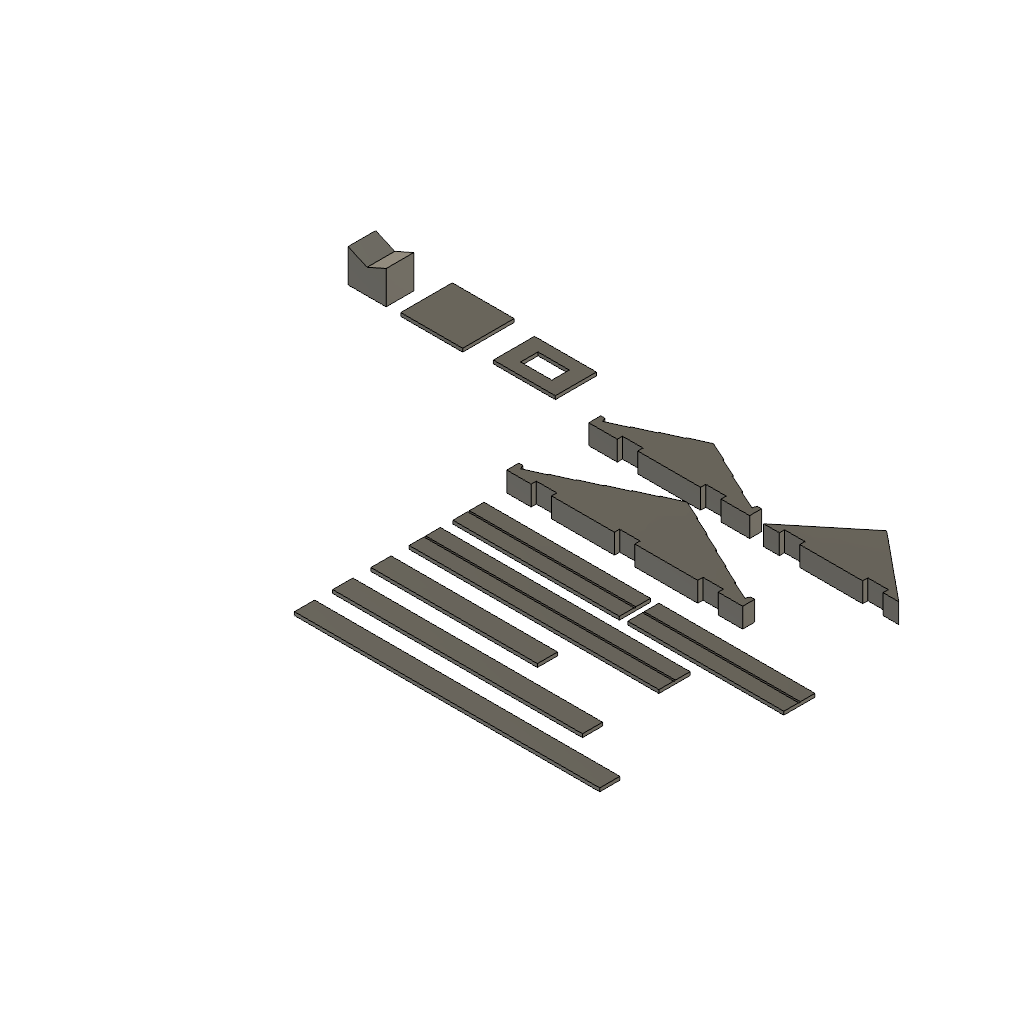
DeadPresidentTreeSections_roof_parts (Autodesk Fusion 360 design; units mm, degrees)
part number: 2026-11-12-23-33-05-956
part number: 2026-11-12-23-33-08-958
part number: 2026-11-12-23-33-09-476
part number: 2026-11-12-23-33-09-794
part number: 2026-11-12-23-33-09-946
part number: 2026-11-12-23-33-10-021
part number: 2026-11-12-23-33-10-090
part number: 2026-11-12-23-33-10-162
part number: 2026-11-12-23-33-10-314
part number: 2026-11-12-23-33-10-475
part number: 2026-11-12-23-33-10-651
part number: 2026-11-12-23-33-10-935
part number: 2026-11-12-23-33-11-042
Autodesk Fusion 360 part; units mm, degrees
sketch "Half profile" plane through (0, 0, 0) normal (0, 0, 1) x (1, 0, 0) in component "gable_plastic_8-1_2"
  line L0 (0, 0) -> (107.95, 0)
  line L1 (107.95, 0) -> (107.95, 57.95)
  line L2 (107.95, 57.95) -> (5.4, 7.5)
  line L3 (5.4, 7.5) -> (3.7975, 11.1)
  line L4 (3.7975, 11.1) -> (0, 11.1)
  line L5 (0, 11.1) -> (0, 0)
  dimension "d46" = 107.95
  dimension "d47" = 57.95
  dimension "d48" = 5.4
  dimension "d49" = 7.5
  dimension "d50" = 3.7975
  dimension "d51" = 11.1
  constraint coincident L0.start L5.end
  constraint horizontal L0.start L0.end
  constraint vertical L0.end L1.end
  constraint vertical L0.start L4.end
  constraint horizontal L3.end L4.end
  measures "d46" horizontal distance of L0.start L0.end
  measures "d47" vertical distance of L0.start L1.end
  measures "d48" horizontal distance of L0.start L2.end
  measures "d49" vertical distance of L0.start L2.end
  measures "d50" horizontal distance of L0.start L3.end
  measures "d51" vertical distance of L0.start L3.end
extrude "Half gable" add sketch "Half profile" along normal blind 18.25 makes body 1 in component "gable_plastic_8-1_2"
sketch "Step" plane through (0, 0, 0) normal (0, 0, 1) x (1, 0, 0) in component "gable_plastic_8-1_2"
  line L0 (5.4, 7.5) -> (22.4917, 15.9083)
  line L1 (22.4917, 15.9083) -> (22.4917, 15.1083)
  line L2 (22.4917, 15.1083) -> (5.4, 7.5)
  dimension "d54" = 5.4
  dimension "d55" = 7.5
  dimension "d56" = 22.4917
  dimension "d57" = 15.9083
  dimension "d58" = 15.1083
  constraint vertical L0.end L1.end
  measures "d54" horizontal distance of origin L0.start
  measures "d55" vertical distance of origin L0.start
  measures "d56" horizontal distance of origin L0.end
  measures "d57" vertical distance of origin L0.end
  measures "d58" vertical distance of origin L1.end
extrude "Step cut" cut sketch "Step" along normal blind 18.25 bodies 1 in component "gable_plastic_8-1_2"
pattern_linear "Step pattern" count 6 spacing 19.048 along (0.897296, 0.441429, 0) count 3 spacing 0 along (0.897296, 0.441429, 0) of "Step cut" in component "gable_plastic_8-1_2"
ref_plane "WorkPlane1" through (107.95, 0, 0) normal (1, 0, 0) x (0, 1, 0) in component "gable_plastic_8-1_2"
mirror "Mirror half" about plane through (107.95, 0, 0) normal (1, 0, 0) of bodies 1 merged in component "gable_plastic_8-1_2"
sketch "Notch" plane through (0, 0, 0) normal (0, 0, 1) x (1, 0, 0) in component "gable_plastic_8-1_2"
  line L0 (22.425, -1) -> (41.075, -1)
  line L1 (41.075, -1) -> (41.075, 4.7625)
  line L2 (41.075, 4.7625) -> (22.425, 4.7625)
  line L3 (22.425, 4.7625) -> (22.425, -1)
  dimension "d69" = 22.425
  dimension "d70" = 1
  dimension "d71" = 41.075
  dimension "d72" = 4.7625
  constraint horizontal L0
  constraint vertical L1
  constraint horizontal L2
  constraint vertical L3
  measures "d69" horizontal distance of origin L0.start
  measures "d70" vertical distance of origin L0.start
  measures "d71" horizontal distance of origin L1.end
  measures "d72" vertical distance of origin L1.end
extrude "Notch cut" cut sketch "Notch" along normal blind 18.25 bodies 1 in component "gable_plastic_8-1_2"
pattern_linear "Notch pattern" count 3 spacing 76.2 along (1, 0, 0) count 3 spacing 0 along (1, 0, 0) of "Notch cut" in component "gable_plastic_8-1_2"
sketch "Half profile (2)" plane through (0, 0, 0) normal (0, 0, 1) x (1, 0, 0) in component "gable_plastic_small_2notch"
  line L0 (0, 0) -> (73.66, 0)
  line L1 (73.66, 0) -> (73.66, 41.3718)
  line L2 (73.66, 41.3718) -> (5.4, 7.5)
  line L3 (5.4, 7.5) -> (3.7824, 11.1)
  line L4 (3.7824, 11.1) -> (0, 11.1)
  line L5 (0, 11.1) -> (0, 0)
  dimension "d79" = 73.66
  dimension "d80" = 41.3718
  dimension "d81" = 5.4
  dimension "d82" = 7.5
  dimension "d83" = 3.7824
  dimension "d84" = 11.1
  constraint coincident L0.start L5.end
  constraint horizontal L0.start L0.end
  constraint vertical L0.end L1.end
  constraint vertical L0.start L4.end
  constraint horizontal L3.end L4.end
  measures "d79" horizontal distance of L0.start L0.end
  measures "d80" vertical distance of L0.start L1.end
  measures "d81" horizontal distance of L0.start L2.end
  measures "d82" vertical distance of L0.start L2.end
  measures "d83" horizontal distance of L0.start L3.end
  measures "d84" vertical distance of L0.start L3.end
extrude "Half gable'" add sketch "Half profile (2)" along normal blind 18.25 separate body makes body 2 in component "gable_plastic_small_2notch"
sketch "Step (2)" plane through (0, 0, 0) normal (0, 0, 1) x (1, 0, 0) in component "gable_plastic_small_2notch"
  line L0 (5.4, 7.5) -> (22.465, 15.968)
  line L1 (22.465, 15.968) -> (22.465, 15.168)
  line L2 (22.465, 15.168) -> (5.4, 7.5)
  dimension "d87" = 5.4
  dimension "d88" = 7.5
  dimension "d89" = 22.465
  dimension "d90" = 15.968
  dimension "d91" = 15.168
  constraint vertical L0.end L1.end
  measures "d87" horizontal distance of origin L0.start
  measures "d88" vertical distance of origin L0.start
  measures "d89" horizontal distance of origin L0.end
  measures "d90" vertical distance of origin L0.end
  measures "d91" vertical distance of origin L1.end
extrude "Step cut'" cut sketch "Step (2)" along normal blind 18.25 bodies 2 in component "gable_plastic_small_2notch"
pattern_linear "Step pattern'" count 4 spacing 19.0505 along (0.895778, 0.444501, 0) count 3 spacing 0 along (0.895778, 0.444501, 0) of "Step cut'" in component "gable_plastic_small_2notch"
ref_plane "WorkPlane1" through (73.66, 0, 0) normal (1, 0, 0) x (0, 1, 0) in component "gable_plastic_small_2notch"
mirror "Mirror half'" about plane through (73.66, 0, 0) normal (1, 0, 0) of bodies 2 merged in component "gable_plastic_small_2notch"
sketch "Notch (2)" plane through (0, 0, 0) normal (0, 0, 1) x (1, 0, 0) in component "gable_plastic_small_2notch"
  line L0 (26.235, -1) -> (44.885, -1)
  line L1 (44.885, -1) -> (44.885, 4.7625)
  line L2 (44.885, 4.7625) -> (26.235, 4.7625)
  line L3 (26.235, 4.7625) -> (26.235, -1)
  dimension "d102" = 26.235
  dimension "d103" = 1
  dimension "d104" = 44.885
  dimension "d105" = 4.7625
  constraint horizontal L0
  constraint vertical L1
  constraint horizontal L2
  constraint vertical L3
  measures "d102" horizontal distance of origin L0.start
  measures "d103" vertical distance of origin L0.start
  measures "d104" horizontal distance of origin L1.end
  measures "d105" vertical distance of origin L1.end
extrude "Notch cut'" cut sketch "Notch (2)" along normal blind 18.25 bodies 2 in component "gable_plastic_small_2notch"
pattern_linear "Notch pattern'" count 2 spacing 76.2 along (1, 0, 0) count 3 spacing 0 along (1, 0, 0) of "Notch cut'" in component "gable_plastic_small_2notch"
sketch "Profile" plane through (0, 0, 0) normal (0, 0, 1) x (1, 0, 0) in component "gable_wood_triangle_4x2"
  line L0 (0, 0) -> (123.825, 0)
  line L1 (123.825, 0) -> (61.9125, 50.8)
  line L2 (61.9125, 50.8) -> (0, 0)
  dimension "d117" = 123.825
  dimension "d118" = 61.9125
  dimension "d119" = 50.8
  constraint coincident L0.start L2.end
  constraint horizontal L0.start L0.end
  measures "d117" horizontal distance of L0.start L0.end
  measures "d118" horizontal distance of L0.start L1.end
  measures "d119" vertical distance of L0.start L1.end
extrude "Gable" add sketch "Profile" along normal blind 18.25 separate body makes body 3 in component "gable_wood_triangle_4x2"
sketch "Notch (3)" plane through (0, 0, 0) normal (0, 0, 1) x (1, 0, 0) in component "gable_wood_triangle_4x2"
  line L0 (14.4875, -1) -> (33.1375, -1)
  line L1 (33.1375, -1) -> (33.1375, 4.7625)
  line L2 (33.1375, 4.7625) -> (14.4875, 4.7625)
  line L3 (14.4875, 4.7625) -> (14.4875, -1)
  dimension "d122" = 14.4875
  dimension "d123" = 1
  dimension "d124" = 33.1375
  dimension "d125" = 4.7625
  constraint horizontal L0
  constraint vertical L1
  constraint horizontal L2
  constraint vertical L3
  measures "d122" horizontal distance of origin L0.start
  measures "d123" vertical distance of origin L0.start
  measures "d124" horizontal distance of origin L1.end
  measures "d125" vertical distance of origin L1.end
extrude "Notch cut''" cut sketch "Notch (3)" along normal blind 18.25 bodies 3 in component "gable_wood_triangle_4x2"
pattern_linear "Notch pattern''" count 2 spacing 76.2 along (1, 0, 0) count 3 spacing 0 along (1, 0, 0) of "Notch cut''" in component "gable_wood_triangle_4x2"
sketch "Outline" plane through (0, 0, 0) normal (0, 0, 1) x (1, 0, 0) in component "shingle_flat_6"
  line L0 (0, -9.25) -> (152.4, -9.25)
  line L1 (152.4, -9.25) -> (152.4, 9.25)
  line L2 (152.4, 9.25) -> (0, 9.25)
  line L3 (0, 9.25) -> (0, -9.25)
  dimension "d133" = 9.25
  dimension "d134" = 152.4
  dimension "d135" = 9.25
  constraint horizontal L0
  constraint vertical L1
  constraint horizontal L2
  constraint vertical L3
  constraint vertical origin L0.start
  measures "d133" vertical distance of origin L0.start
  measures "d134" horizontal distance of origin L1.end
  measures "d135" vertical distance of origin L1.end
extrude "Board" add sketch "Outline" along normal blind 3.175 separate body makes body 4 in component "shingle_flat_6"
sketch "Outline (2)" plane through (0, 0, 0) normal (0, 0, 1) x (1, 0, 0) in component "shingle_flat_9"
  line L0 (0, -9.25) -> (228.6, -9.25)
  line L1 (228.6, -9.25) -> (228.6, 9.25)
  line L2 (228.6, 9.25) -> (0, 9.25)
  line L3 (0, 9.25) -> (0, -9.25)
  dimension "d139" = 9.25
  dimension "d140" = 228.6
  dimension "d141" = 9.25
  constraint horizontal L0
  constraint vertical L1
  constraint horizontal L2
  constraint vertical L3
  constraint vertical origin L0.start
  measures "d139" vertical distance of origin L0.start
  measures "d140" horizontal distance of origin L1.end
  measures "d141" vertical distance of origin L1.end
extrude "Board'" add sketch "Outline (2)" along normal blind 3.175 separate body makes body 5 in component "shingle_flat_9"
sketch "Outline (3)" plane through (0, 0, 0) normal (0, 0, 1) x (1, 0, 0) in component "shingle_flat_11"
  line L0 (0, -9.25) -> (279.4, -9.25)
  line L1 (279.4, -9.25) -> (279.4, 9.25)
  line L2 (279.4, 9.25) -> (0, 9.25)
  line L3 (0, 9.25) -> (0, -9.25)
  dimension "d145" = 9.25
  dimension "d146" = 279.4
  dimension "d147" = 9.25
  constraint horizontal L0
  constraint vertical L1
  constraint horizontal L2
  constraint vertical L3
  constraint vertical origin L0.start
  measures "d145" vertical distance of origin L0.start
  measures "d146" horizontal distance of origin L1.end
  measures "d147" vertical distance of origin L1.end
extrude "Board''" add sketch "Outline (3)" along normal blind 3.175 separate body makes body 6 in component "shingle_flat_11"
sketch "Outline (4)" plane through (0, 0, 0) normal (0, 0, 1) x (1, 0, 0) in component "shingle_ridge_5-5_8"
  line L0 (0, -14.2875) -> (142.875, -14.2875)
  line L1 (142.875, -14.2875) -> (142.875, 14.2875)
  line L2 (142.875, 14.2875) -> (0, 14.2875)
  line L3 (0, 14.2875) -> (0, -14.2875)
  dimension "d151" = 14.2875
  dimension "d152" = 142.875
  dimension "d153" = 14.2875
  constraint horizontal L0
  constraint vertical L1
  constraint horizontal L2
  constraint vertical L3
  constraint vertical origin L0.start
  measures "d151" vertical distance of origin L0.start
  measures "d152" horizontal distance of origin L1.end
  measures "d153" vertical distance of origin L1.end
extrude "Board'''" add sketch "Outline (4)" along normal blind 3.175 separate body makes body 7 in component "shingle_ridge_5-5_8"
sketch "Groove" plane through (0, 0, 0) normal (1, 0, 0) x (0, 0, -1) in component "shingle_ridge_5-5_8"
  line L0 (-3.175, -0.8) -> (-3.175, 0.8)
  line L1 (-3.175, 0.8) -> (-2.375, 0)
  line L2 (-2.375, 0) -> (-3.175, -0.8)
  dimension "d156" = 0.8
  dimension "d157" = 3.175
  dimension "d158" = 0.8
  dimension "d159" = 2.375
  constraint vertical L0.start L0.end
  constraint horizontal origin L1.end
  measures "d156" vertical distance of origin L0.start
  measures "d157" horizontal distance of origin L0.start
  measures "d158" vertical distance of origin L0.end
  measures "d159" horizontal distance of origin L1.end
extrude "Groove (1)" cut sketch "Groove" along normal blind 142.875 bodies 7 in component "shingle_ridge_5-5_8"
sketch "Outline (5)" plane through (0, 0, 0) normal (0, 0, 1) x (1, 0, 0) in component "shingle_ridge_6"
  line L0 (0, -14.2875) -> (152.4, -14.2875)
  line L1 (152.4, -14.2875) -> (152.4, 14.2875)
  line L2 (152.4, 14.2875) -> (0, 14.2875)
  line L3 (0, 14.2875) -> (0, -14.2875)
  dimension "d163" = 14.2875
  dimension "d164" = 152.4
  dimension "d165" = 14.2875
  constraint horizontal L0
  constraint vertical L1
  constraint horizontal L2
  constraint vertical L3
  constraint vertical origin L0.start
  measures "d163" vertical distance of origin L0.start
  measures "d164" horizontal distance of origin L1.end
  measures "d165" vertical distance of origin L1.end
extrude "Board''''" add sketch "Outline (5)" along normal blind 3.175 separate body makes body 8 in component "shingle_ridge_6"
sketch "Groove (2)" plane through (0, 0, 0) normal (1, 0, 0) x (0, 0, -1) in component "shingle_ridge_6"
  line L0 (-3.175, -0.8) -> (-3.175, 0.8)
  line L1 (-3.175, 0.8) -> (-2.375, 0)
  line L2 (-2.375, 0) -> (-3.175, -0.8)
  dimension "d168" = 0.8
  dimension "d169" = 3.175
  dimension "d170" = 0.8
  dimension "d171" = 2.375
  constraint vertical L0.start L0.end
  constraint horizontal origin L1.end
  measures "d168" vertical distance of origin L0.start
  measures "d169" horizontal distance of origin L0.start
  measures "d170" vertical distance of origin L0.end
  measures "d171" horizontal distance of origin L1.end
extrude "Groove (1)'" cut sketch "Groove (2)" along normal blind 152.4 bodies 8 in component "shingle_ridge_6"
sketch "Outline (6)" plane through (0, 0, 0) normal (0, 0, 1) x (1, 0, 0) in component "shingle_ridge_9"
  line L0 (0, -14.2875) -> (228.6, -14.2875)
  line L1 (228.6, -14.2875) -> (228.6, 14.2875)
  line L2 (228.6, 14.2875) -> (0, 14.2875)
  line L3 (0, 14.2875) -> (0, -14.2875)
  dimension "d175" = 14.2875
  dimension "d176" = 228.6
  dimension "d177" = 14.2875
  constraint horizontal L0
  constraint vertical L1
  constraint horizontal L2
  constraint vertical L3
  constraint vertical origin L0.start
  measures "d175" vertical distance of origin L0.start
  measures "d176" horizontal distance of origin L1.end
  measures "d177" vertical distance of origin L1.end
extrude "Board'''''" add sketch "Outline (6)" along normal blind 3.175 separate body makes body 9 in component "shingle_ridge_9"
sketch "Groove (3)" plane through (0, 0, 0) normal (1, 0, 0) x (0, 0, -1) in component "shingle_ridge_9"
  line L0 (-3.175, -0.8) -> (-3.175, 0.8)
  line L1 (-3.175, 0.8) -> (-2.375, 0)
  line L2 (-2.375, 0) -> (-3.175, -0.8)
  dimension "d180" = 0.8
  dimension "d181" = 3.175
  dimension "d182" = 0.8
  dimension "d183" = 2.375
  constraint vertical L0.start L0.end
  constraint horizontal origin L1.end
  measures "d180" vertical distance of origin L0.start
  measures "d181" horizontal distance of origin L0.start
  measures "d182" vertical distance of origin L0.end
  measures "d183" horizontal distance of origin L1.end
extrude "Groove (1)''" cut sketch "Groove (3)" along normal blind 228.6 bodies 9 in component "shingle_ridge_9"
sketch "Outline (7)" plane through (0, 0, 0) normal (0, 0, 1) x (1, 0, 0) in component "chimney"
  line L0 (-17.4625, -12.7) -> (17.4625, -12.7)
  line L1 (17.4625, -12.7) -> (17.4625, 12.7)
  line L2 (17.4625, 12.7) -> (-17.4625, 12.7)
  line L3 (-17.4625, 12.7) -> (-17.4625, -12.7)
  dimension "d192" = 17.4625
  dimension "d193" = 12.7
  dimension "d194" = 17.4625
  dimension "d195" = 12.7
  constraint horizontal L0
  constraint vertical L1
  constraint horizontal L2
  constraint vertical L3
  measures "d192" horizontal distance of origin L0.start
  measures "d193" vertical distance of origin L0.start
  measures "d194" horizontal distance of origin L1.end
  measures "d195" vertical distance of origin L1.end
extrude "Block" add sketch "Outline (7)" along normal blind 30.48 separate body makes body 10 in component "chimney"
sketch "Pocket" plane through (0, 0, 0) normal (0, 0, 1) x (1, 0, 0) in component "chimney"
  line L0 (-14.4145, -9.652) -> (14.4145, -9.652)
  line L1 (14.4145, -9.652) -> (14.4145, 9.652)
  line L2 (14.4145, 9.652) -> (-14.4145, 9.652)
  line L3 (-14.4145, 9.652) -> (-14.4145, -9.652)
  dimension "d198" = 14.4145
  dimension "d199" = 9.652
  dimension "d200" = 14.4145
  dimension "d201" = 9.652
  constraint horizontal L0
  constraint vertical L1
  constraint horizontal L2
  constraint vertical L3
  measures "d198" horizontal distance of origin L0.start
  measures "d199" vertical distance of origin L0.start
  measures "d200" horizontal distance of origin L1.end
  measures "d201" vertical distance of origin L1.end
extrude "Open top" cut sketch "Pocket" along normal blind 12.7 bodies 10 in component "chimney"
sketch "Ridge V" plane through (0, 0, 0) normal (0, 1, 0) x (1, 0, 0) in component "chimney"
  line L0 (-17.4625, -30.48) -> (17.4625, -30.48)
  line L1 (17.4625, -30.48) -> (0, -22.7066)
  line L2 (0, -22.7066) -> (-17.4625, -30.48)
  dimension "d204" = 17.4625
  dimension "d205" = 30.48
  dimension "d206" = 17.4625
  dimension "d207" = 22.7066
  constraint horizontal L0.start L0.end
  constraint vertical origin L1.end
  measures "d204" horizontal distance of origin L0.start
  measures "d205" vertical distance of origin L0.start
  measures "d206" horizontal distance of origin L0.end
  measures "d207" vertical distance of origin L1.end
extrude "Ridge V cut" cut sketch "Ridge V" along normal mid plane 27.4 bodies 10 in component "chimney"
sketch "Outline (8)" plane through (0, 0, 0) normal (0, 0, 1) x (1, 0, 0) in component "extra_door"
  line L0 (-28.375, -23.6125) -> (28.375, -23.6125)
  line L1 (28.375, -23.6125) -> (28.375, 23.6125)
  line L2 (28.375, 23.6125) -> (-28.375, 23.6125)
  line L3 (-28.375, 23.6125) -> (-28.375, -23.6125)
  dimension "d213" = 28.375
  dimension "d214" = 23.6125
  dimension "d215" = 28.375
  dimension "d216" = 23.6125
  constraint horizontal L0
  constraint vertical L1
  constraint horizontal L2
  constraint vertical L3
  measures "d213" horizontal distance of origin L0.start
  measures "d214" vertical distance of origin L0.start
  measures "d215" horizontal distance of origin L1.end
  measures "d216" vertical distance of origin L1.end
extrude "Panel" add sketch "Outline (8)" along normal blind 3.175 separate body makes body 11 in component "extra_door"
sketch "Outline (9)" plane through (0, 0, 0) normal (0, 0, 1) x (1, 0, 0) in component "extra_window"
  line L0 (-28.375, -18.85) -> (28.375, -18.85)
  line L1 (28.375, -18.85) -> (28.375, 18.85)
  line L2 (28.375, 18.85) -> (-28.375, 18.85)
  line L3 (-28.375, 18.85) -> (-28.375, -18.85)
  line L4 (-14.2875, -7.9375) -> (14.2875, -7.9375)
  line L5 (14.2875, -7.9375) -> (14.2875, 7.9375)
  line L6 (14.2875, 7.9375) -> (-14.2875, 7.9375)
  line L7 (-14.2875, 7.9375) -> (-14.2875, -7.9375)
  dimension "d224" = 28.375
  dimension "d225" = 18.85
  dimension "d226" = 28.375
  dimension "d227" = 18.85
  dimension "d228" = 14.2875
  dimension "d229" = 7.9375
  dimension "d230" = 14.2875
  dimension "d231" = 7.9375
  constraint horizontal L0
  constraint vertical L1
  constraint horizontal L2
  constraint vertical L3
  constraint horizontal L4
  constraint vertical L5
  constraint horizontal L6
  constraint vertical L7
  measures "d224" horizontal distance of origin L0.start
  measures "d225" vertical distance of origin L0.start
  measures "d226" horizontal distance of origin L1.end
  measures "d227" vertical distance of origin L1.end
  measures "d228" horizontal distance of origin L4.start
  measures "d229" vertical distance of origin L4.start
  measures "d230" horizontal distance of origin L5.end
  measures "d231" vertical distance of origin L5.end
extrude "Panel'" add sketch "Outline (9)" along normal blind 3.175 separate body makes body 12 in component "extra_window"
component "gable_plastic_8-1_2" placed x (1, 0, 0) y (0, 1, 0) z (0, 0, 1) at (320, 185, 0)
component "gable_plastic_small_2notch" placed x (1, 0, 0) y (0, 1, 0) z (0, 0, 1) at (320, 260, 0)
component "gable_wood_triangle_4x2" placed x (1, 0, 0) y (0, 1, 0) z (0, 0, 1) at (480, 260, 0)
component "shingle_flat_6" placed x (1, 0, 0) y (0, 1, 0) z (0, 0, 1) at (320, 70, 0)
component "shingle_flat_9" placed x (1, 0, 0) y (0, 1, 0) z (0, 0, 1) at (320, 35, 0)
component "shingle_flat_11" placed x (1, 0, 0) y (0, 1, 0) z (0, 0, 1) at (320, 0, 0)
component "shingle_ridge_5-5_8" placed x (1, 0, 0) y (0, 1, 0) z (0, 0, 1) at (480, 150, 0)
component "shingle_ridge_6" placed x (1, 0, 0) y (0, 1, 0) z (0, 0, 1) at (320, 150, 0)
component "shingle_ridge_9" placed x (1, 0, 0) y (0, 1, 0) z (0, 0, 1) at (320, 110, 0)
component "chimney" placed x (1, 0, 0) y (0, 1, 0) z (0, 0, 1) at (100, 290, 0)
component "extra_door" placed x (1, 0, 0) y (0, 1, 0) z (0, 0, 1) at (160, 300, 0)
component "extra_window" placed x (1, 0, 0) y (0, 1, 0) z (0, 0, 1) at (240, 300, 0)
component "(Unsaved)" placed x (1, 0, 0) y (0, 1, 0) z (0, 0, 1) at (0, 0, 0) in component "shingle_flat_11"
equation "LogDia = 0.75 in" comment "Log diameter (across the flats of an octagonal log)"
equation "NotchDepth = 0.1875 in" comment "Notch depth, each side of a log"
equation "NotchCenters = 3 in" comment "Spacing between notch centres"
equation "Clearance = 0.2 mm" comment "Fit clearance per side. Try 0.3 mm for PETG"
equation "PrintFlat = 0.8 mm" comment "Total width taken off a log, as an equal flat on each side; one is the bed side"
equation "MateWidth = LogDia - PrintFlat" comment "Width of a log, half log or gable where it sits in a notch"
equation "NotchWidth = MateWidth + 2 * Clearance" comment "Notch width (mating width plus clearance on each side)"
equation "CourseRise = LogDia - 2 * NotchDepth" comment "Height gained per crossing course"
equation "HalfLogHeight = LogDia - NotchDepth" comment "Half-log height (flat sits at the notch floor)"
equation "GableThk = MateWidth" comment "Gable thickness (fills a notch like a log)"
equation "ShingleThk = 0.125 in" comment "Shingle thickness"
equation "FlatShingleWidth = 18.5 mm" comment "Flat shingle width: one fits each step of a plastic gable"
equation "RidgeShingleWidth = 1.125 in" comment "Ridge shingle width"
equation "RidgeGrooveWidth = 1.6 mm" comment "Ridge shingle centre groove width"
equation "RidgeGrooveDepth = 0.8 mm" comment "Ridge shingle centre groove depth"
equation "PanelThk = 0.125 in" comment "Door and window panel thickness"
equation "GableL_Width = 8.5 in" comment "Overall width"
equation "GableL_Notches = 3" comment "Number of notch positions"
equation "GableL_FirstNotch = ( GableL_Width - ( GableL_Notches - 1 ) * NotchCenters ) / 2" comment "Centre of the first notch (keeps the row of notches centred)"
equation "GableL_NotchStep = NotchCenters * min(1; GableL_Notches - 1) + 0.001 mm * ( 1 - min(1; GableL_Notches - 1) )" comment "Pattern step: NotchCenters, or about zero when there is only one notch"
equation "GableL_Steps = 6" comment "Roof steps per side"
equation "GableL_EaveHeight = 7.5 mm" comment "Height of the slope start above the base"
equation "GableL_LipThk = 5.4 mm" comment "Eave lip thickness"
equation "GableL_LipHeight = 3.6 mm" comment "Eave lip height above the slope start"
equation "GableL_Riser = 0.8 mm" comment "Vertical riser of each roof step; lower than a shingle is thick, so shingles butt edge to edge"
equation "GableL_StepRun = ( GableL_Width / 2 - GableL_LipThk ) / GableL_Steps" comment "Horizontal run of one step"
equation "GableL_Height = 2.25 in" comment "Overall height at the peak"
equation "GableL_TreadRise = ( GableL_Height - GableL_EaveHeight - ( GableL_Steps - 1 ) * GableL_Riser ) / GableL_Steps" comment "Rise of one sloped tread"
equation "GableL_StepPitch = sqrt(GableL_StepRun ^ 2 + ( GableL_TreadRise + GableL_Riser ) ^ 2)" comment "Step spacing measured along the slope"
equation "GableL_TreadLen = sqrt(GableL_StepRun ^ 2 + GableL_TreadRise ^ 2)" comment "Length of one tread: a flat shingle lies on it, so it must exceed FlatShingleWidth"
equation "PlasticRoofAngle = atan(GableL_TreadRise / GableL_StepRun)" comment "Angle the shingles lie at on the large plastic gable. The chimney follows it"
equation "GableS_Width = 5.8 in" comment "Overall width"
equation "GableS_Notches = 2" comment "Number of notch positions"
equation "GableS_FirstNotch = ( GableS_Width - ( GableS_Notches - 1 ) * NotchCenters ) / 2" comment "Centre of the first notch (keeps the row of notches centred)"
equation "GableS_NotchStep = NotchCenters * min(1; GableS_Notches - 1) + 0.001 mm * ( 1 - min(1; GableS_Notches - 1) )" comment "Pattern step: NotchCenters, or about zero when there is only one notch"
equation "GableS_Steps = 4" comment "Roof steps per side"
equation "GableS_EaveHeight = 7.5 mm" comment "Height of the slope start above the base"
equation "GableS_LipThk = 5.4 mm" comment "Eave lip thickness"
equation "GableS_LipHeight = 3.6 mm" comment "Eave lip height above the slope start"
equation "GableS_Riser = 0.8 mm" comment "Vertical riser of each roof step; lower than a shingle is thick, so shingles butt edge to edge"
equation "GableS_StepRun = ( GableS_Width / 2 - GableS_LipThk ) / GableS_Steps" comment "Horizontal run of one step"
equation "GableS_Height = GableS_EaveHeight + GableS_Steps * sqrt(GableL_TreadLen ^ 2 - GableS_StepRun ^ 2) + ( GableS_Steps - 1 ) * GableS_Riser" comment "Overall height at the peak"
equation "GableS_TreadRise = ( GableS_Height - GableS_EaveHeight - ( GableS_Steps - 1 ) * GableS_Riser ) / GableS_Steps" comment "Rise of one sloped tread"
equation "GableS_StepPitch = sqrt(GableS_StepRun ^ 2 + ( GableS_TreadRise + GableS_Riser ) ^ 2)" comment "Step spacing measured along the slope"
equation "GableS_TreadLen = sqrt(GableS_StepRun ^ 2 + GableS_TreadRise ^ 2)" comment "Length of one tread: a flat shingle lies on it, so it must exceed FlatShingleWidth"
equation "d46 = GableL_Width / 2"
equation "d47 = GableL_Height + GableL_Riser"
equation "d48 = GableL_LipThk"
equation "d49 = GableL_EaveHeight"
equation "d50 = GableL_LipThk - GableL_LipHeight * GableL_TreadRise / GableL_StepRun"
equation "d51 = GableL_EaveHeight + GableL_LipHeight"
equation "d52 = GableThk"
equation "d54 = GableL_LipThk"
equation "d55 = GableL_EaveHeight"
equation "d56 = GableL_LipThk + GableL_StepRun"
equation "d57 = GableL_EaveHeight + GableL_TreadRise + GableL_Riser"
equation "d58 = GableL_EaveHeight + GableL_TreadRise"
equation "d59 = GableThk"
equation "d61 = GableL_Steps"
equation "d63 = GableL_StepPitch"
equation "d65 = GableL_Width / 2"
equation "d69 = GableL_FirstNotch - NotchWidth / 2"
equation "d71 = GableL_FirstNotch + NotchWidth / 2"
equation "d72 = NotchDepth"
equation "d73 = GableThk"
equation "d75 = max(GableL_Notches; 2)"
equation "d77 = GableL_NotchStep"
equation "d79 = GableS_Width / 2"
equation "d80 = GableS_Height + GableS_Riser"
equation "d81 = GableS_LipThk"
equation "d82 = GableS_EaveHeight"
equation "d83 = GableS_LipThk - GableS_LipHeight * GableS_TreadRise / GableS_StepRun"
equation "d84 = GableS_EaveHeight + GableS_LipHeight"
equation "d85 = GableThk"
equation "d87 = GableS_LipThk"
equation "d88 = GableS_EaveHeight"
equation "d89 = GableS_LipThk + GableS_StepRun"
equation "d90 = GableS_EaveHeight + GableS_TreadRise + GableS_Riser"
equation "d91 = GableS_EaveHeight + GableS_TreadRise"
equation "d92 = GableThk"
equation "d94 = GableS_Steps"
equation "d96 = GableS_StepPitch"
equation "d98 = GableS_Width / 2"
equation "d102 = GableS_FirstNotch - NotchWidth / 2"
equation "d104 = GableS_FirstNotch + NotchWidth / 2"
equation "d105 = NotchDepth"
equation "d106 = GableThk"
equation "d108 = max(GableS_Notches; 2)"
equation "d110 = GableS_NotchStep"
equation "GableTri_Width = 4.875 in" comment "Overall width"
equation "GableTri_Notches = 2" comment "Number of notch positions"
equation "GableTri_FirstNotch = ( GableTri_Width - ( GableTri_Notches - 1 ) * NotchCenters ) / 2" comment "Centre of the first notch (keeps the row of notches centred)"
equation "GableTri_NotchStep = NotchCenters * min(1; GableTri_Notches - 1) + 0.001 mm * ( 1 - min(1; GableTri_Notches - 1) )" comment "Pattern step: NotchCenters, or about zero when there is only one notch"
equation "GableTri_Height = 2 in" comment "Height at the peak"
equation "d117 = GableTri_Width"
equation "d118 = GableTri_Width / 2"
equation "d119 = GableTri_Height"
equation "d120 = GableThk"
equation "d122 = GableTri_FirstNotch - NotchWidth / 2"
equation "d124 = GableTri_FirstNotch + NotchWidth / 2"
equation "d125 = NotchDepth"
equation "d126 = GableThk"
equation "d128 = max(GableTri_Notches; 2)"
equation "d130 = GableTri_NotchStep"
equation "ShFlat6_Length = 6 in" comment "Length"
equation "d133 = FlatShingleWidth / 2"
equation "d134 = ShFlat6_Length"
equation "d135 = FlatShingleWidth / 2"
equation "d136 = ShingleThk"
equation "ShFlat9_Length = 9 in" comment "Length"
equation "d139 = FlatShingleWidth / 2"
equation "d140 = ShFlat9_Length"
equation "d141 = FlatShingleWidth / 2"
equation "d142 = ShingleThk"
equation "ShFlat11_Length = 11 in" comment "Length"
equation "d145 = FlatShingleWidth / 2"
equation "d146 = ShFlat11_Length"
equation "d147 = FlatShingleWidth / 2"
equation "d148 = ShingleThk"
equation "ShRidge5_Length = 5.625 in" comment "Length"
equation "d151 = RidgeShingleWidth / 2"
equation "d152 = ShRidge5_Length"
equation "d153 = RidgeShingleWidth / 2"
equation "d154 = ShingleThk"
equation "d156 = RidgeGrooveWidth / 2"
equation "d157 = ShingleThk"
equation "d158 = RidgeGrooveWidth / 2"
equation "d159 = ShingleThk - RidgeGrooveDepth"
equation "d160 = ShRidge5_Length"
equation "ShRidge6_Length = 6 in" comment "Length"
equation "d163 = RidgeShingleWidth / 2"
equation "d164 = ShRidge6_Length"
equation "d165 = RidgeShingleWidth / 2"
equation "d166 = ShingleThk"
equation "d168 = RidgeGrooveWidth / 2"
equation "d169 = ShingleThk"
equation "d170 = RidgeGrooveWidth / 2"
equation "d171 = ShingleThk - RidgeGrooveDepth"
equation "d172 = ShRidge6_Length"
equation "ShRidge9_Length = 9 in" comment "Length"
equation "d175 = RidgeShingleWidth / 2"
equation "d176 = ShRidge9_Length"
equation "d177 = RidgeShingleWidth / 2"
equation "d178 = ShingleThk"
equation "d180 = RidgeGrooveWidth / 2"
equation "d181 = ShingleThk"
equation "d182 = RidgeGrooveWidth / 2"
equation "d183 = ShingleThk - RidgeGrooveDepth"
equation "d184 = ShRidge9_Length"
equation "Chimney_Width = 1.375 in" comment "Width across the ridge"
equation "Chimney_Depth = 1 in" comment "Depth along the ridge"
equation "Chimney_Height = 1.2 in" comment "Overall height"
equation "Chimney_Wall = 0.12 in" comment "Wall thickness of the open top"
equation "Chimney_Pocket = 0.5 in" comment "Depth of the open top"
equation "Chimney_VDepth = Chimney_Width / 2 * tan(PlasticRoofAngle)" comment "Depth of the V cut that straddles the ridge"
equation "d192 = Chimney_Width / 2"
equation "d193 = Chimney_Depth / 2"
equation "d194 = Chimney_Width / 2"
equation "d195 = Chimney_Depth / 2"
equation "d196 = Chimney_Height"
equation "d198 = Chimney_Width / 2 - Chimney_Wall"
equation "d199 = Chimney_Depth / 2 - Chimney_Wall"
equation "d200 = Chimney_Width / 2 - Chimney_Wall"
equation "d201 = Chimney_Depth / 2 - Chimney_Wall"
equation "d202 = Chimney_Pocket"
equation "d204 = Chimney_Width / 2"
equation "d205 = Chimney_Height"
equation "d206 = Chimney_Width / 2"
equation "d207 = Chimney_Height - Chimney_VDepth"
equation "d208 = Chimney_Depth + 2 mm"
equation "Door_Courses = 4" comment "Log courses the panel spans"
equation "Door_Width = NotchCenters - LogDia - 2 * Clearance" comment "Width (fits the gap between crossing logs)"
equation "Door_Height = ( Door_Courses - 1 ) * CourseRise + LogDia - 2 * Clearance" comment "Height"
equation "d213 = Door_Width / 2"
equation "d214 = Door_Height / 2"
equation "d215 = Door_Width / 2"
equation "d216 = Door_Height / 2"
equation "d217 = PanelThk"
equation "Window_Courses = 3" comment "Log courses the panel spans"
equation "Window_Width = NotchCenters - LogDia - 2 * Clearance" comment "Width (fits the gap between crossing logs)"
equation "Window_Height = ( Window_Courses - 1 ) * CourseRise + LogDia - 2 * Clearance" comment "Height"
equation "Window_OpeningWidth = 1.125 in" comment "Opening width"
equation "Window_OpeningHeight = 0.625 in" comment "Opening height"
equation "d224 = Window_Width / 2"
equation "d225 = Window_Height / 2"
equation "d226 = Window_Width / 2"
equation "d227 = Window_Height / 2"
equation "d228 = Window_OpeningWidth / 2"
equation "d229 = Window_OpeningHeight / 2"
equation "d230 = Window_OpeningWidth / 2"
equation "d231 = Window_OpeningHeight / 2"
equation "d232 = PanelThk"
named bodies: "gable_plastic_8-1_2", "gable_plastic_small_2notch", "gable_wood_triangle_4x2", "shingle_flat_6", "shingle_flat_9", "shingle_flat_11", "shingle_ridge_5-5_8", "shingle_ridge_6", "shingle_ridge_9", "chimney", "extra_door", "extra_window"
